Autodesk Fusion 360 part; units mm, degrees
(part 2 of 2)
equation "d231 = rf_voffset_Ref"
equation "d232 = rf_hoffset_Ref"
equation "d233 = rf_voffset_Ref"
equation "d234 = rf_hoffset_Ref"
equation "d235 = rf_voffset_Ref"
equation "d236 = rf_hoffset_Ref"
equation "d237 = rf_diameter_Ref"
equation "d238 = rf_diameter_Ref"
equation "d239 = rf_diameter_Ref"
equation "d240 = rf_diameter_Ref"
equation "d243 = -rf_width_Ref"
equation "d246 = case_side_fillet_Ref"
equation "case_side_fillet_Ref = 2.5 mm"
equation "case_top_fillet_Ref = 0.5 mm"
equation "case_top_inner_border_side_fillet_Ref = 1.5 mm"
equation "case_top_inner_border_top_fillet_Ref = 1 mm"
equation "usbc_contour_height_Ref = 4.5 mm"
equation "usbc_contour_length_Ref = 12 mm"
equation "assemblyscr_head_diameter_Ref = 4.15 mm"
equation "assemblyscr_head_width_Ref = 0.85 mm"
equation "rf_diameter_Ref = 10 mm"
equation "rf_width_Ref = 0.5 mm"
equation "rf_voffset_Ref = case_border_width_Ref + 10 mm"
equation "rf_hoffset_Ref = case_border_width_Ref + 15 mm"
